OPEN_LOUD_A0_E03 (Autodesk Fusion 360 design; units mm, degrees)
part number: 2026-11-09-21-09-22-943
part number: 2026-11-09-21-09-23-218
part number: 2026-11-09-21-09-23-288
part number: 2026-11-09-21-09-23-386
part number: 2026-11-09-21-09-23-510
part number: 2026-11-09-21-09-23-669
part number: 2026-11-09-21-09-23-859
part number: 2026-11-09-21-09-24-690
part number: 2026-11-09-21-09-37-670
part number: 2026-11-09-21-09-45-890
part number: 2026-11-09-21-09-47-234
part number: 2026-11-09-21-09-48-583
part number: 2026-11-09-21-09-49-964
part number: 2026-11-09-21-09-52-239
part number: 2026-11-09-21-09-53-688
part number: 2026-11-09-21-09-55-178
part number: 2026-11-09-21-09-56-657
part number: 2026-11-09-21-09-58-092
part number: 2026-11-09-21-10-02-668
part number: 2026-11-09-21-10-08-469
part number: 2026-11-09-21-10-09-806
part number: 2026-11-09-21-14-51-726
part number: 2026-11-09-21-15-00-511
part number: 2026-11-09-21-15-10-046
part number: 2026-11-09-21-15-20-423
part number: 2026-11-09-21-15-31-572
part number: 2026-11-09-21-15-43-577
part number: 2026-11-09-21-15-56-782
part number: 2026-11-09-21-16-10-440
part number: 2026-11-09-21-16-24-862
part number: 2026-11-09-21-16-40-177
Autodesk Fusion 360 part; units mm, degrees
(part 1 of 3)
ref_plane "Arbeitsebene1" through (0, 0, 0) normal (0, 0, 1) x (1, 0, 0) in component "Side_left"
sketch "Skizze1" plane through (0, 0, 0) normal (0, 0, 1) x (1, 0, 0) in component "Side_left"
  line L0 (0, 0) -> (12, 0)
  line L1 (12, 0) -> (12, 560)
  line L2 (12, 560) -> (0, 560)
  line L3 (0, 560) -> (0, 0)
  dimension "d63" = 12
  dimension "d64" = 560
  constraint horizontal L0
  constraint horizontal L2
  constraint vertical L1
  constraint vertical L3
  constraint coincident L0.start L3.end
  measures "d63" horizontal distance of L0.start L0.end
  measures "d64" vertical distance of L0.end L1.end
extrude "Side_left" add sketch "Skizze1" along normal blind 300 makes body 1 in component "Side_left"
ref_plane "Arbeitsebene1" through (0, 0, 0) normal (0, 0, 1) x (1, 0, 0) in component "Side_right"
sketch "Skizze1 (2)" plane through (0, 0, 0) normal (0, 0, 1) x (1, 0, 0) in component "Side_right"
  line L0 (318, 0) -> (330, 0)
  line L1 (330, 0) -> (330, 560)
  line L2 (330, 560) -> (318, 560)
  line L3 (318, 560) -> (318, 0)
  dimension "d69" = 318
  dimension "d70" = 12
  dimension "d71" = 560
  constraint horizontal L0
  constraint horizontal L2
  constraint vertical L1
  constraint vertical L3
  constraint horizontal origin L0.start
  measures "d69" horizontal distance of origin L0.start
  measures "d70" horizontal distance of L0.start L0.end
  measures "d71" vertical distance of L0.end L1.end
extrude "Side_right" add sketch "Skizze1 (2)" along normal blind 300 separate body makes body 2 in component "Side_right"
ref_plane "Arbeitsebene1" through (0, 0, 0) normal (0, 0, 1) x (1, 0, 0) in component "Bottom"
sketch "Skizze1 (3)" plane through (0, 0, 0) normal (0, 0, 1) x (1, 0, 0) in component "Bottom"
  line L0 (12, 0) -> (318, 0)
  line L1 (318, 0) -> (318, 12)
  line L2 (318, 12) -> (12, 12)
  line L3 (12, 12) -> (12, 0)
  dimension "d76" = 12
  dimension "d77" = 306
  dimension "d78" = 12
  constraint horizontal L0
  constraint horizontal L2
  constraint vertical L1
  constraint vertical L3
  constraint horizontal origin L0.start
  measures "d76" horizontal distance of origin L0.start
  measures "d77" horizontal distance of L0.start L0.end
  measures "d78" vertical distance of L0.end L1.end
extrude "Bottom" add sketch "Skizze1 (3)" along normal blind 300 separate body makes body 3 in component "Bottom"
ref_plane "Arbeitsebene1" through (0, 0, 0) normal (0, 0, 1) x (1, 0, 0) in component "Top"
sketch "Skizze1 (4)" plane through (0, 0, 0) normal (0, 0, 1) x (1, 0, 0) in component "Top"
  line L0 (12, 548) -> (318, 548)
  line L1 (318, 548) -> (318, 560)
  line L2 (318, 560) -> (12, 560)
  line L3 (12, 560) -> (12, 548)
  dimension "d83" = 12
  dimension "d84" = 548
  dimension "d85" = 306
  dimension "d86" = 12
  constraint horizontal L0
  constraint horizontal L2
  constraint vertical L1
  constraint vertical L3
  measures "d83" horizontal distance of origin L0.start
  measures "d84" vertical distance of origin L0.start
  measures "d85" horizontal distance of L0.start L0.end
  measures "d86" vertical distance of L0.end L1.end
extrude "Top" add sketch "Skizze1 (4)" along normal blind 300 separate body makes body 4 in component "Top"
ref_plane "Arbeitsebene1" through (0, 0, 0) normal (0, 0, 1) x (1, 0, 0) in component "Baffle"
sketch "Skizze1 (5)" plane through (0, 0, 0) normal (0, 0, 1) x (1, 0, 0) in component "Baffle"
  line L0 (12, 12) -> (318, 12)
  line L1 (318, 12) -> (318, 548)
  line L2 (318, 548) -> (12, 548)
  line L3 (12, 548) -> (12, 12)
  dimension "d91" = 12
  dimension "d92" = 12
  dimension "d93" = 306
  dimension "d94" = 536
  constraint horizontal L0
  constraint horizontal L2
  constraint vertical L1
  constraint vertical L3
  measures "d91" horizontal distance of origin L0.start
  measures "d92" vertical distance of origin L0.start
  measures "d93" horizontal distance of L0.start L0.end
  measures "d94" vertical distance of L0.end L1.end
extrude "Baffle" add sketch "Skizze1 (5)" along normal blind 12 separate body makes body 5 in component "Baffle"
ref_plane "Arbeitsebene1" through (0, 0, 288) normal (0, 0, 1) x (1, 0, 0) in component "Rear_removable"
sketch "Skizze1 (6)" plane through (0, 0, 288) normal (0, 0, 1) x (1, 0, 0) in component "Rear_removable"
  line L0 (12, 12) -> (318, 12)
  line L1 (318, 12) -> (318, 548)
  line L2 (318, 548) -> (12, 548)
  line L3 (12, 548) -> (12, 12)
  dimension "d99" = 12
  dimension "d100" = 12
  dimension "d101" = 306
  dimension "d102" = 536
  constraint horizontal L0
  constraint horizontal L2
  constraint vertical L1
  constraint vertical L3
  measures "d99" horizontal distance of origin L0.start
  measures "d100" vertical distance of origin L0.start
  measures "d101" horizontal distance of L0.start L0.end
  measures "d102" vertical distance of L0.end L1.end
extrude "Rear_removable" add sketch "Skizze1 (6)" along normal blind 12 separate body makes body 6 in component "Rear_removable"
ref_plane "Arbeitsebene2" through (0, 0, 0) normal (0, 0, 1) x (1, 0, 0) in component "Baffle"
sketch "Skizze2" plane through (0, 0, 0) normal (0, 0, 1) x (1, 0, 0) in component "Baffle"
  circle A0 centre (165, 260) radius 117.15
  dimension "d107" = 165
  dimension "d108" = 260
  dimension "d109" = 234.3
  measures "d107" horizontal distance of origin A0.centre
  measures "d108" vertical distance of origin A0.centre
  measures "d109" diameter of A0
extrude "LF_cut" cut sketch "Skizze2" along normal blind 12 bodies 5 in component "Baffle"
ref_plane "Arbeitsebene3" through (0, 0, 0) normal (0, 0, 1) x (1, 0, 0) in component "Baffle"
sketch "Skizze3" plane through (0, 0, 0) normal (0, 0, 1) x (1, 0, 0) in component "Baffle"
  circle A0 centre (165, 70) radius 48.9864
  dimension "d114" = 165
  dimension "d115" = 70
  dimension "d116" = 97.9728
  measures "d114" horizontal distance of origin A0.centre
  measures "d115" vertical distance of origin A0.centre
  measures "d116" diameter of A0
extrude "Port_cut" cut sketch "Skizze3" along normal blind 12 bodies 5 in component "Baffle"
ref_plane "Arbeitsebene4" through (0, 0, 0) normal (0, 0, 1) x (1, 0, 0) in component "Baffle"
sketch "Skizze4" plane through (0, 0, 0) normal (0, 0, 1) x (1, 0, 0) in component "Baffle"
  line L0 (113, 418) -> (217, 418)
  line L1 (217, 418) -> (217, 522)
  line L2 (217, 522) -> (113, 522)
  line L3 (113, 522) -> (113, 418)
  dimension "d121" = 113
  dimension "d122" = 418
  dimension "d123" = 104
  dimension "d124" = 104
  constraint horizontal L0
  constraint horizontal L2
  constraint vertical L1
  constraint vertical L3
  measures "d121" horizontal distance of origin L0.start
  measures "d122" vertical distance of origin L0.start
  measures "d123" horizontal distance of L0.start L0.end
  measures "d124" vertical distance of L0.end L1.end
extrude "Horn_cut" cut sketch "Skizze4" along normal blind 12 bodies 5 in component "Baffle"
ref_plane "Arbeitsebene1" through (0, 0, 12) normal (0, 0, 1) x (1, 0, 0) in component "Baffle_inner_lamination"
sketch "Skizze1 (7)" plane through (0, 0, 12) normal (0, 0, 1) x (1, 0, 0) in component "Baffle_inner_lamination"
  line L0 (12, 12) -> (318, 12)
  line L1 (318, 12) -> (318, 548)
  line L2 (318, 548) -> (12, 548)
  line L3 (12, 548) -> (12, 12)
  dimension "d129" = 12
  dimension "d130" = 12
  dimension "d131" = 306
  dimension "d132" = 536
  constraint horizontal L0
  constraint horizontal L2
  constraint vertical L1
  constraint vertical L3
  measures "d129" horizontal distance of origin L0.start
  measures "d130" vertical distance of origin L0.start
  measures "d131" horizontal distance of L0.start L0.end
  measures "d132" vertical distance of L0.end L1.end
extrude "Baffle_inner_lamination" add sketch "Skizze1 (7)" along normal blind 12 separate body makes body 7 in component "Baffle_inner_lamination"
ref_plane "Arbeitsebene2" through (0, 0, 12) normal (0, 0, 1) x (1, 0, 0) in component "Baffle_inner_lamination"
sketch "Skizze2 (2)" plane through (0, 0, 12) normal (0, 0, 1) x (1, 0, 0) in component "Baffle_inner_lamination"
  circle A0 centre (165, 260) radius 117.15
  dimension "d137" = 165
  dimension "d138" = 260
  dimension "d139" = 234.3
  measures "d137" horizontal distance of origin A0.centre
  measures "d138" vertical distance of origin A0.centre
  measures "d139" diameter of A0
extrude "LF_reinforcement_cut" cut sketch "Skizze2 (2)" along normal blind 12 bodies 7 in component "Baffle_inner_lamination"
ref_plane "Arbeitsebene3" through (0, 0, 12) normal (0, 0, 1) x (1, 0, 0) in component "Baffle_inner_lamination"
sketch "Skizze3 (2)" plane through (0, 0, 12) normal (0, 0, 1) x (1, 0, 0) in component "Baffle_inner_lamination"
  circle A0 centre (165, 70) radius 48.9864
  dimension "d144" = 165
  dimension "d145" = 70
  dimension "d146" = 97.9728
  measures "d144" horizontal distance of origin A0.centre
  measures "d145" vertical distance of origin A0.centre
  measures "d146" diameter of A0
extrude "Port_reinforcement_cut" cut sketch "Skizze3 (2)" along normal blind 12 bodies 7 in component "Baffle_inner_lamination"
ref_plane "Arbeitsebene4" through (0, 0, 12) normal (0, 0, 1) x (1, 0, 0) in component "Baffle_inner_lamination"
sketch "Skizze4 (2)" plane through (0, 0, 12) normal (0, 0, 1) x (1, 0, 0) in component "Baffle_inner_lamination"
  line L0 (113, 418) -> (217, 418)
  line L1 (217, 418) -> (217, 522)
  line L2 (217, 522) -> (113, 522)
  line L3 (113, 522) -> (113, 418)
  dimension "d151" = 113
  dimension "d152" = 418
  dimension "d153" = 104
  dimension "d154" = 104
  constraint horizontal L0
  constraint horizontal L2
  constraint vertical L1
  constraint vertical L3
  measures "d151" horizontal distance of origin L0.start
  measures "d152" vertical distance of origin L0.start
  measures "d153" horizontal distance of L0.start L0.end
  measures "d154" vertical distance of L0.end L1.end
extrude "Horn_reinforcement_cut" cut sketch "Skizze4 (2)" along normal blind 12 bodies 7 in component "Baffle_inner_lamination"
ref_plane "Arbeitsebene5" through (0, 0, 0) normal (0, 0, 1) x (1, 0, 0) in component "Baffle"
sketch "Skizze5" plane through (0, 0, 0) normal (0, 0, 1) x (1, 0, 0) in component "Baffle"
  circle A0 centre (286.9, 260) radius 2.75
  dimension "d159" = 286.9
  dimension "d160" = 260
  dimension "d161" = 5.5
  measures "d159" horizontal distance of origin A0.centre
  measures "d160" vertical distance of origin A0.centre
  measures "d161" diameter of A0
extrude "LF_M5_bore_0" cut sketch "Skizze5" along normal blind 12 bodies 5 in component "Baffle"
ref_plane "Arbeitsebene6" through (0, 0, 0) normal (0, 0, 1) x (1, 0, 0) in component "Baffle"
sketch "Skizze6" plane through (0, 0, 0) normal (0, 0, 1) x (1, 0, 0) in component "Baffle"
  circle A0 centre (251.1963, 346.1963) radius 2.75
  dimension "d166" = 251.1963
  dimension "d167" = 346.1963
  dimension "d168" = 5.5
  measures "d166" horizontal distance of origin A0.centre
  measures "d167" vertical distance of origin A0.centre
  measures "d168" diameter of A0
extrude "LF_M5_bore_1" cut sketch "Skizze6" along normal blind 12 bodies 5 in component "Baffle"
ref_plane "Arbeitsebene7" through (0, 0, 0) normal (0, 0, 1) x (1, 0, 0) in component "Baffle"
sketch "Skizze7" plane through (0, 0, 0) normal (0, 0, 1) x (1, 0, 0) in component "Baffle"
  circle A0 centre (165, 381.9) radius 2.75
  dimension "d173" = 165
  dimension "d174" = 381.9
  dimension "d175" = 5.5
  measures "d173" horizontal distance of origin A0.centre
  measures "d174" vertical distance of origin A0.centre
  measures "d175" diameter of A0
extrude "LF_M5_bore_2" cut sketch "Skizze7" along normal blind 12 bodies 5 in component "Baffle"
ref_plane "Arbeitsebene8" through (0, 0, 0) normal (0, 0, 1) x (1, 0, 0) in component "Baffle"
sketch "Skizze8" plane through (0, 0, 0) normal (0, 0, 1) x (1, 0, 0) in component "Baffle"
  circle A0 centre (78.8037, 346.1963) radius 2.75
  dimension "d180" = 78.8037
  dimension "d181" = 346.1963
  dimension "d182" = 5.5
  measures "d180" horizontal distance of origin A0.centre
  measures "d181" vertical distance of origin A0.centre
  measures "d182" diameter of A0
extrude "LF_M5_bore_3" cut sketch "Skizze8" along normal blind 12 bodies 5 in component "Baffle"
ref_plane "Arbeitsebene9" through (0, 0, 0) normal (0, 0, 1) x (1, 0, 0) in component "Baffle"
sketch "Skizze9" plane through (0, 0, 0) normal (0, 0, 1) x (1, 0, 0) in component "Baffle"
  circle A0 centre (43.1, 260) radius 2.75
  dimension "d187" = 43.1
  dimension "d188" = 260
  dimension "d189" = 5.5
  measures "d187" horizontal distance of origin A0.centre
  measures "d188" vertical distance of origin A0.centre
  measures "d189" diameter of A0
extrude "LF_M5_bore_4" cut sketch "Skizze9" along normal blind 12 bodies 5 in component "Baffle"
ref_plane "Arbeitsebene10" through (0, 0, 0) normal (0, 0, 1) x (1, 0, 0) in component "Baffle"
sketch "Skizze10" plane through (0, 0, 0) normal (0, 0, 1) x (1, 0, 0) in component "Baffle"
  circle A0 centre (78.8037, 173.8037) radius 2.75
  dimension "d194" = 78.8037
  dimension "d195" = 173.8037
  dimension "d196" = 5.5
  measures "d194" horizontal distance of origin A0.centre
  measures "d195" vertical distance of origin A0.centre
  measures "d196" diameter of A0
extrude "LF_M5_bore_5" cut sketch "Skizze10" along normal blind 12 bodies 5 in component "Baffle"
ref_plane "Arbeitsebene11" through (0, 0, 0) normal (0, 0, 1) x (1, 0, 0) in component "Baffle"
sketch "Skizze11" plane through (0, 0, 0) normal (0, 0, 1) x (1, 0, 0) in component "Baffle"
  circle A0 centre (165, 138.1) radius 2.75
  dimension "d201" = 165
  dimension "d202" = 138.1
  dimension "d203" = 5.5
  measures "d201" horizontal distance of origin A0.centre
  measures "d202" vertical distance of origin A0.centre
  measures "d203" diameter of A0
extrude "LF_M5_bore_6" cut sketch "Skizze11" along normal blind 12 bodies 5 in component "Baffle"
ref_plane "Arbeitsebene12" through (0, 0, 0) normal (0, 0, 1) x (1, 0, 0) in component "Baffle"
sketch "Skizze12" plane through (0, 0, 0) normal (0, 0, 1) x (1, 0, 0) in component "Baffle"
  circle A0 centre (251.1963, 173.8037) radius 2.75
  dimension "d208" = 251.1963
  dimension "d209" = 173.8037
  dimension "d210" = 5.5
  measures "d208" horizontal distance of origin A0.centre
  measures "d209" vertical distance of origin A0.centre
  measures "d210" diameter of A0
extrude "LF_M5_bore_7" cut sketch "Skizze12" along normal blind 12 bodies 5 in component "Baffle"
ref_plane "Arbeitsebene13" through (0, 0, 0) normal (0, 0, 1) x (1, 0, 0) in component "Baffle"
sketch "Skizze13" plane through (0, 0, 0) normal (0, 0, 1) x (1, 0, 0) in component "Baffle"
  circle A0 centre (108, 413) radius 2.25
  dimension "d215" = 108
  dimension "d216" = 413
  dimension "d217" = 4.5
  measures "d215" horizontal distance of origin A0.centre
  measures "d216" vertical distance of origin A0.centre
  measures "d217" diameter of A0
extrude "Horn_M4_bore" cut sketch "Skizze13" along normal blind 12 bodies 5 in component "Baffle"
ref_plane "Arbeitsebene14" through (0, 0, 0) normal (0, 0, 1) x (1, 0, 0) in component "Baffle"
sketch "Skizze14" plane through (0, 0, 0) normal (0, 0, 1) x (1, 0, 0) in component "Baffle"
  circle A0 centre (108, 527) radius 2.25
  dimension "d222" = 108
  dimension "d223" = 527
  dimension "d224" = 4.5
  measures "d222" horizontal distance of origin A0.centre
  measures "d223" vertical distance of origin A0.centre
  measures "d224" diameter of A0
extrude "Horn_M4_bore (1)" cut sketch "Skizze14" along normal blind 12 bodies 5 in component "Baffle"
ref_plane "Arbeitsebene15" through (0, 0, 0) normal (0, 0, 1) x (1, 0, 0) in component "Baffle"
sketch "Skizze15" plane through (0, 0, 0) normal (0, 0, 1) x (1, 0, 0) in component "Baffle"
  circle A0 centre (222, 413) radius 2.25
  dimension "d229" = 222
  dimension "d230" = 413
  dimension "d231" = 4.5
  measures "d229" horizontal distance of origin A0.centre
  measures "d230" vertical distance of origin A0.centre
  measures "d231" diameter of A0
extrude "Horn_M4_bore (2)" cut sketch "Skizze15" along normal blind 12 bodies 5 in component "Baffle"
ref_plane "Arbeitsebene16" through (0, 0, 0) normal (0, 0, 1) x (1, 0, 0) in component "Baffle"
sketch "Skizze16" plane through (0, 0, 0) normal (0, 0, 1) x (1, 0, 0) in component "Baffle"
  circle A0 centre (222, 527) radius 2.25
  dimension "d236" = 222
  dimension "d237" = 527
  dimension "d238" = 4.5
  measures "d236" horizontal distance of origin A0.centre
  measures "d237" vertical distance of origin A0.centre
  measures "d238" diameter of A0
extrude "Horn_M4_bore (3)" cut sketch "Skizze16" along normal blind 12 bodies 5 in component "Baffle"
ref_plane "Arbeitsebene5" through (0, 0, 12) normal (0, 0, 1) x (1, 0, 0) in component "Baffle_inner_lamination"
sketch "Skizze5 (2)" plane through (0, 0, 12) normal (0, 0, 1) x (1, 0, 0) in component "Baffle_inner_lamination"
  circle A0 centre (286.9, 260) radius 2.75
  dimension "d243" = 286.9
  dimension "d244" = 260
  dimension "d245" = 5.5
  measures "d243" horizontal distance of origin A0.centre
  measures "d244" vertical distance of origin A0.centre
  measures "d245" diameter of A0
extrude "LF_M5_bore_0'" cut sketch "Skizze5 (2)" along normal blind 12 bodies 7 in component "Baffle_inner_lamination"
ref_plane "Arbeitsebene6" through (0, 0, 12) normal (0, 0, 1) x (1, 0, 0) in component "Baffle_inner_lamination"
sketch "Skizze6 (2)" plane through (0, 0, 12) normal (0, 0, 1) x (1, 0, 0) in component "Baffle_inner_lamination"
  circle A0 centre (251.1963, 346.1963) radius 2.75
  dimension "d250" = 251.1963
  dimension "d251" = 346.1963
  dimension "d252" = 5.5
  measures "d250" horizontal distance of origin A0.centre
  measures "d251" vertical distance of origin A0.centre
  measures "d252" diameter of A0
extrude "LF_M5_bore_1'" cut sketch "Skizze6 (2)" along normal blind 12 bodies 7 in component "Baffle_inner_lamination"
ref_plane "Arbeitsebene7" through (0, 0, 12) normal (0, 0, 1) x (1, 0, 0) in component "Baffle_inner_lamination"
sketch "Skizze7 (2)" plane through (0, 0, 12) normal (0, 0, 1) x (1, 0, 0) in component "Baffle_inner_lamination"
  circle A0 centre (165, 381.9) radius 2.75
  dimension "d257" = 165
  dimension "d258" = 381.9
  dimension "d259" = 5.5
  measures "d257" horizontal distance of origin A0.centre
  measures "d258" vertical distance of origin A0.centre
  measures "d259" diameter of A0
extrude "LF_M5_bore_2'" cut sketch "Skizze7 (2)" along normal blind 12 bodies 7 in component "Baffle_inner_lamination"
ref_plane "Arbeitsebene8" through (0, 0, 12) normal (0, 0, 1) x (1, 0, 0) in component "Baffle_inner_lamination"
sketch "Skizze8 (2)" plane through (0, 0, 12) normal (0, 0, 1) x (1, 0, 0) in component "Baffle_inner_lamination"
  circle A0 centre (78.8037, 346.1963) radius 2.75
  dimension "d264" = 78.8037
  dimension "d265" = 346.1963
  dimension "d266" = 5.5
  measures "d264" horizontal distance of origin A0.centre
  measures "d265" vertical distance of origin A0.centre
  measures "d266" diameter of A0
extrude "LF_M5_bore_3'" cut sketch "Skizze8 (2)" along normal blind 12 bodies 7 in component "Baffle_inner_lamination"
ref_plane "Arbeitsebene9" through (0, 0, 12) normal (0, 0, 1) x (1, 0, 0) in component "Baffle_inner_lamination"
sketch "Skizze9 (2)" plane through (0, 0, 12) normal (0, 0, 1) x (1, 0, 0) in component "Baffle_inner_lamination"
  circle A0 centre (43.1, 260) radius 2.75
  dimension "d271" = 43.1
  dimension "d272" = 260
  dimension "d273" = 5.5
  measures "d271" horizontal distance of origin A0.centre
  measures "d272" vertical distance of origin A0.centre
  measures "d273" diameter of A0
extrude "LF_M5_bore_4'" cut sketch "Skizze9 (2)" along normal blind 12 bodies 7 in component "Baffle_inner_lamination"
ref_plane "Arbeitsebene10" through (0, 0, 12) normal (0, 0, 1) x (1, 0, 0) in component "Baffle_inner_lamination"
sketch "Skizze10 (2)" plane through (0, 0, 12) normal (0, 0, 1) x (1, 0, 0) in component "Baffle_inner_lamination"
  circle A0 centre (78.8037, 173.8037) radius 2.75
  dimension "d278" = 78.8037
  dimension "d279" = 173.8037
  dimension "d280" = 5.5
  measures "d278" horizontal distance of origin A0.centre
  measures "d279" vertical distance of origin A0.centre
  measures "d280" diameter of A0
extrude "LF_M5_bore_5'" cut sketch "Skizze10 (2)" along normal blind 12 bodies 7 in component "Baffle_inner_lamination"
ref_plane "Arbeitsebene11" through (0, 0, 12) normal (0, 0, 1) x (1, 0, 0) in component "Baffle_inner_lamination"
sketch "Skizze11 (2)" plane through (0, 0, 12) normal (0, 0, 1) x (1, 0, 0) in component "Baffle_inner_lamination"
  circle A0 centre (165, 138.1) radius 2.75
  dimension "d285" = 165
  dimension "d286" = 138.1
  dimension "d287" = 5.5
  measures "d285" horizontal distance of origin A0.centre
  measures "d286" vertical distance of origin A0.centre
  measures "d287" diameter of A0
extrude "LF_M5_bore_6'" cut sketch "Skizze11 (2)" along normal blind 12 bodies 7 in component "Baffle_inner_lamination"
ref_plane "Arbeitsebene12" through (0, 0, 12) normal (0, 0, 1) x (1, 0, 0) in component "Baffle_inner_lamination"
sketch "Skizze12 (2)" plane through (0, 0, 12) normal (0, 0, 1) x (1, 0, 0) in component "Baffle_inner_lamination"
  circle A0 centre (251.1963, 173.8037) radius 2.75
  dimension "d292" = 251.1963
  dimension "d293" = 173.8037
  dimension "d294" = 5.5
  measures "d292" horizontal distance of origin A0.centre
  measures "d293" vertical distance of origin A0.centre
  measures "d294" diameter of A0
extrude "LF_M5_bore_7'" cut sketch "Skizze12 (2)" along normal blind 12 bodies 7 in component "Baffle_inner_lamination"
ref_plane "Arbeitsebene13" through (0, 0, 12) normal (0, 0, 1) x (1, 0, 0) in component "Baffle_inner_lamination"
sketch "Skizze13 (2)" plane through (0, 0, 12) normal (0, 0, 1) x (1, 0, 0) in component "Baffle_inner_lamination"
  circle A0 centre (108, 413) radius 2.25
  dimension "d299" = 108
  dimension "d300" = 413
  dimension "d301" = 4.5
  measures "d299" horizontal distance of origin A0.centre
  measures "d300" vertical distance of origin A0.centre
  measures "d301" diameter of A0
extrude "Horn_M4_bore'" cut sketch "Skizze13 (2)" along normal blind 12 bodies 7 in component "Baffle_inner_lamination"
ref_plane "Arbeitsebene14" through (0, 0, 12) normal (0, 0, 1) x (1, 0, 0) in component "Baffle_inner_lamination"
sketch "Skizze14 (2)" plane through (0, 0, 12) normal (0, 0, 1) x (1, 0, 0) in component "Baffle_inner_lamination"
  circle A0 centre (108, 527) radius 2.25
  dimension "d306" = 108
  dimension "d307" = 527
  dimension "d308" = 4.5
  measures "d306" horizontal distance of origin A0.centre
  measures "d307" vertical distance of origin A0.centre
  measures "d308" diameter of A0
extrude "Horn_M4_bore (1)'" cut sketch "Skizze14 (2)" along normal blind 12 bodies 7 in component "Baffle_inner_lamination"
ref_plane "Arbeitsebene15" through (0, 0, 12) normal (0, 0, 1) x (1, 0, 0) in component "Baffle_inner_lamination"
sketch "Skizze15 (2)" plane through (0, 0, 12) normal (0, 0, 1) x (1, 0, 0) in component "Baffle_inner_lamination"
  circle A0 centre (222, 413) radius 2.25
  dimension "d313" = 222
  dimension "d314" = 413
  dimension "d315" = 4.5
  measures "d313" horizontal distance of origin A0.centre
  measures "d314" vertical distance of origin A0.centre
  measures "d315" diameter of A0
extrude "Horn_M4_bore (2)'" cut sketch "Skizze15 (2)" along normal blind 12 bodies 7 in component "Baffle_inner_lamination"
ref_plane "Arbeitsebene16" through (0, 0, 12) normal (0, 0, 1) x (1, 0, 0) in component "Baffle_inner_lamination"
sketch "Skizze16 (2)" plane through (0, 0, 12) normal (0, 0, 1) x (1, 0, 0) in component "Baffle_inner_lamination"
  circle A0 centre (222, 527) radius 2.25
  dimension "d320" = 222
  dimension "d321" = 527
  dimension "d322" = 4.5
  measures "d320" horizontal distance of origin A0.centre
  measures "d321" vertical distance of origin A0.centre
  measures "d322" diameter of A0
extrude "Horn_M4_bore (3)'" cut sketch "Skizze16 (2)" along normal blind 12 bodies 7 in component "Baffle_inner_lamination"
ref_plane "Arbeitsebene1" through (0, 0, 24) normal (0, 0, 1) x (1, 0, 0) in component "LF_steel_backing_ring_candidate"
sketch "Skizze1 (8)" plane through (0, 0, 24) normal (0, 0, 1) x (1, 0, 0) in component "LF_steel_backing_ring_candidate"
  circle A0 centre (165, 260) radius 140
  circle A1 centre (165, 260) radius 110
  dimension "d327" = 165
  dimension "d328" = 260
  dimension "d329" = 280
  dimension "d330" = 220
  constraint concentric A0 A1
  measures "d327" horizontal distance of origin A0.centre
  measures "d328" vertical distance of origin A0.centre
  measures "d329" diameter of A0
  measures "d330" diameter of A1
extrude "Steel_backing_ring" add sketch "Skizze1 (8)" along normal blind 3 separate body makes body 8 in component "LF_steel_backing_ring_candidate"
ref_plane "Arbeitsebene2" through (0, 0, 24) normal (0, 0, 1) x (1, 0, 0) in component "LF_steel_backing_ring_candidate"
sketch "Skizze2 (3)" plane through (0, 0, 24) normal (0, 0, 1) x (1, 0, 0) in component "LF_steel_backing_ring_candidate"
  circle A0 centre (165, 70) radius 49.4864
  dimension "d335" = 165
  dimension "d336" = 70
  dimension "d337" = 98.9728
  measures "d335" horizontal distance of origin A0.centre
  measures "d336" vertical distance of origin A0.centre
  measures "d337" diameter of A0
ref_plane "Arbeitsebene3" through (0, 0, 24) normal (0, 0, 1) x (1, 0, 0) in component "LF_steel_backing_ring_candidate"
sketch "Skizze3 (3)" plane through (0, 0, 24) normal (0, 0, 1) x (1, 0, 0) in component "LF_steel_backing_ring_candidate"
  circle A0 centre (286.9, 260) radius 2.75
  dimension "d342" = 286.9
  dimension "d343" = 260
  dimension "d344" = 5.5
  measures "d342" horizontal distance of origin A0.centre
  measures "d343" vertical distance of origin A0.centre
  measures "d344" diameter of A0
extrude "Steel_M5_bore_0" cut sketch "Skizze3 (3)" along normal blind 3 bodies 8 in component "LF_steel_backing_ring_candidate"
ref_plane "Arbeitsebene4" through (0, 0, 24) normal (0, 0, 1) x (1, 0, 0) in component "LF_steel_backing_ring_candidate"
sketch "Skizze4 (3)" plane through (0, 0, 24) normal (0, 0, 1) x (1, 0, 0) in component "LF_steel_backing_ring_candidate"
  circle A0 centre (251.1963, 346.1963) radius 2.75
  dimension "d349" = 251.1963
  dimension "d350" = 346.1963
  dimension "d351" = 5.5
  measures "d349" horizontal distance of origin A0.centre
  measures "d350" vertical distance of origin A0.centre
  measures "d351" diameter of A0
extrude "Steel_M5_bore_1" cut sketch "Skizze4 (3)" along normal blind 3 bodies 8 in component "LF_steel_backing_ring_candidate"
ref_plane "Arbeitsebene5" through (0, 0, 24) normal (0, 0, 1) x (1, 0, 0) in component "LF_steel_backing_ring_candidate"
sketch "Skizze5 (3)" plane through (0, 0, 24) normal (0, 0, 1) x (1, 0, 0) in component "LF_steel_backing_ring_candidate"
  circle A0 centre (165, 381.9) radius 2.75
  dimension "d356" = 165
  dimension "d357" = 381.9
  dimension "d358" = 5.5
  measures "d356" horizontal distance of origin A0.centre
  measures "d357" vertical distance of origin A0.centre
  measures "d358" diameter of A0
extrude "Steel_M5_bore_2" cut sketch "Skizze5 (3)" along normal blind 3 bodies 8 in component "LF_steel_backing_ring_candidate"
ref_plane "Arbeitsebene6" through (0, 0, 24) normal (0, 0, 1) x (1, 0, 0) in component "LF_steel_backing_ring_candidate"
sketch "Skizze6 (3)" plane through (0, 0, 24) normal (0, 0, 1) x (1, 0, 0) in component "LF_steel_backing_ring_candidate"
  circle A0 centre (78.8037, 346.1963) radius 2.75
  dimension "d363" = 78.8037
  dimension "d364" = 346.1963
  dimension "d365" = 5.5
  measures "d363" horizontal distance of origin A0.centre
  measures "d364" vertical distance of origin A0.centre
  measures "d365" diameter of A0
extrude "Steel_M5_bore_3" cut sketch "Skizze6 (3)" along normal blind 3 bodies 8 in component "LF_steel_backing_ring_candidate"
ref_plane "Arbeitsebene7" through (0, 0, 24) normal (0, 0, 1) x (1, 0, 0) in component "LF_steel_backing_ring_candidate"
sketch "Skizze7 (3)" plane through (0, 0, 24) normal (0, 0, 1) x (1, 0, 0) in component "LF_steel_backing_ring_candidate"
  circle A0 centre (43.1, 260) radius 2.75
  dimension "d370" = 43.1
  dimension "d371" = 260
  dimension "d372" = 5.5
  measures "d370" horizontal distance of origin A0.centre
  measures "d371" vertical distance of origin A0.centre
  measures "d372" diameter of A0
extrude "Steel_M5_bore_4" cut sketch "Skizze7 (3)" along normal blind 3 bodies 8 in component "LF_steel_backing_ring_candidate"
ref_plane "Arbeitsebene8" through (0, 0, 24) normal (0, 0, 1) x (1, 0, 0) in component "LF_steel_backing_ring_candidate"
sketch "Skizze8 (3)" plane through (0, 0, 24) normal (0, 0, 1) x (1, 0, 0) in component "LF_steel_backing_ring_candidate"
  circle A0 centre (78.8037, 173.8037) radius 2.75
  dimension "d377" = 78.8037
  dimension "d378" = 173.8037
  dimension "d379" = 5.5
  measures "d377" horizontal distance of origin A0.centre
  measures "d378" vertical distance of origin A0.centre
  measures "d379" diameter of A0
extrude "Steel_M5_bore_5" cut sketch "Skizze8 (3)" along normal blind 3 bodies 8 in component "LF_steel_backing_ring_candidate"
ref_plane "Arbeitsebene9" through (0, 0, 24) normal (0, 0, 1) x (1, 0, 0) in component "LF_steel_backing_ring_candidate"
sketch "Skizze9 (3)" plane through (0, 0, 24) normal (0, 0, 1) x (1, 0, 0) in component "LF_steel_backing_ring_candidate"
  circle A0 centre (165, 138.1) radius 2.75
  dimension "d384" = 165
  dimension "d385" = 138.1
  dimension "d386" = 5.5
  measures "d384" horizontal distance of origin A0.centre
  measures "d385" vertical distance of origin A0.centre
  measures "d386" diameter of A0
extrude "Steel_M5_bore_6" cut sketch "Skizze9 (3)" along normal blind 3 bodies 8 in component "LF_steel_backing_ring_candidate"
ref_plane "Arbeitsebene10" through (0, 0, 24) normal (0, 0, 1) x (1, 0, 0) in component "LF_steel_backing_ring_candidate"
sketch "Skizze10 (3)" plane through (0, 0, 24) normal (0, 0, 1) x (1, 0, 0) in component "LF_steel_backing_ring_candidate"
  circle A0 centre (251.1963, 173.8037) radius 2.75
  dimension "d391" = 251.1963
  dimension "d392" = 173.8037
  dimension "d393" = 5.5
  measures "d391" horizontal distance of origin A0.centre
  measures "d392" vertical distance of origin A0.centre
  measures "d393" diameter of A0
extrude "Steel_M5_bore_7" cut sketch "Skizze10 (3)" along normal blind 3 bodies 8 in component "LF_steel_backing_ring_candidate"
ref_plane "Arbeitsebene1" through (0, 0, 268) normal (0, 0, 1) x (1, 0, 0) in component "Rear_cleat_left"
sketch "Skizze1 (9)" plane through (0, 0, 268) normal (0, 0, 1) x (1, 0, 0) in component "Rear_cleat_left"
  line L0 (12, 12) -> (32, 12)
  line L1 (32, 12) -> (32, 548)
  line L2 (32, 548) -> (12, 548)
  line L3 (12, 548) -> (12, 12)
  dimension "d398" = 12
  dimension "d399" = 12
  dimension "d400" = 20
  dimension "d401" = 536
  constraint horizontal L0
  constraint horizontal L2
  constraint vertical L1
  constraint vertical L3
  measures "d398" horizontal distance of origin L0.start
  measures "d399" vertical distance of origin L0.start
  measures "d400" horizontal distance of L0.start L0.end
  measures "d401" vertical distance of L0.end L1.end
extrude "Rear_cleat_left" add sketch "Skizze1 (9)" along normal blind 20 separate body makes body 9 in component "Rear_cleat_left"
ref_plane "Arbeitsebene1" through (0, 0, 268) normal (0, 0, 1) x (1, 0, 0) in component "Rear_cleat_right"
sketch "Skizze1 (10)" plane through (0, 0, 268) normal (0, 0, 1) x (1, 0, 0) in component "Rear_cleat_right"
  line L0 (298, 12) -> (318, 12)
  line L1 (318, 12) -> (318, 548)
  line L2 (318, 548) -> (298, 548)
  line L3 (298, 548) -> (298, 12)
  dimension "d406" = 298
  dimension "d407" = 12
  dimension "d408" = 20
  dimension "d409" = 536
  constraint horizontal L0
  constraint horizontal L2
  constraint vertical L1
  constraint vertical L3
  measures "d406" horizontal distance of origin L0.start
  measures "d407" vertical distance of origin L0.start
  measures "d408" horizontal distance of L0.start L0.end
  measures "d409" vertical distance of L0.end L1.end
extrude "Rear_cleat_right" add sketch "Skizze1 (10)" along normal blind 20 separate body makes body 10 in component "Rear_cleat_right"
ref_plane "Arbeitsebene1" through (0, 0, 268) normal (0, 0, 1) x (1, 0, 0) in component "Rear_cleat_bottom"
sketch "Skizze1 (11)" plane through (0, 0, 268) normal (0, 0, 1) x (1, 0, 0) in component "Rear_cleat_bottom"
  line L0 (32, 12) -> (298, 12)
  line L1 (298, 12) -> (298, 32)
  line L2 (298, 32) -> (32, 32)
  line L3 (32, 32) -> (32, 12)
  dimension "d414" = 32
  dimension "d415" = 12
  dimension "d416" = 266
  dimension "d417" = 20
  constraint horizontal L0
  constraint horizontal L2
  constraint vertical L1
  constraint vertical L3
  measures "d414" horizontal distance of origin L0.start
  measures "d415" vertical distance of origin L0.start
  measures "d416" horizontal distance of L0.start L0.end
  measures "d417" vertical distance of L0.end L1.end
extrude "Rear_cleat_bottom" add sketch "Skizze1 (11)" along normal blind 20 separate body makes body 11 in component "Rear_cleat_bottom"
ref_plane "Arbeitsebene1" through (0, 0, 268) normal (0, 0, 1) x (1, 0, 0) in component "Rear_cleat_top"
sketch "Skizze1 (12)" plane through (0, 0, 268) normal (0, 0, 1) x (1, 0, 0) in component "Rear_cleat_top"
  line L0 (32, 528) -> (298, 528)
  line L1 (298, 528) -> (298, 548)
  line L2 (298, 548) -> (32, 548)
  line L3 (32, 548) -> (32, 528)
  dimension "d422" = 32
  dimension "d423" = 528
  dimension "d424" = 266
  dimension "d425" = 20
  constraint horizontal L0
  constraint horizontal L2
  constraint vertical L1
  constraint vertical L3
  measures "d422" horizontal distance of origin L0.start
  measures "d423" vertical distance of origin L0.start
  measures "d424" horizontal distance of L0.start L0.end
  measures "d425" vertical distance of L0.end L1.end
extrude "Rear_cleat_top" add sketch "Skizze1 (12)" along normal blind 20 separate body makes body 12 in component "Rear_cleat_top"
ref_plane "Arbeitsebene1" through (0, 0, 165.9015) normal (0, 0, 1) x (1, 0, 0) in component "Service_partition"
sketch "Skizze1 (13)" plane through (0, 0, 165.9015) normal (0, 0, 1) x (1, 0, 0) in component "Service_partition"
  line L0 (12, 362) -> (318, 362)
  line L1 (318, 362) -> (318, 548)
  line L2 (318, 548) -> (12, 548)
  line L3 (12, 548) -> (12, 362)
  dimension "d430" = 12
  dimension "d431" = 362
  dimension "d432" = 306
  dimension "d433" = 186
  constraint horizontal L0
  constraint horizontal L2
  constraint vertical L1
  constraint vertical L3
  measures "d430" horizontal distance of origin L0.start
  measures "d431" vertical distance of origin L0.start
  measures "d432" horizontal distance of L0.start L0.end
  measures "d433" vertical distance of L0.end L1.end
extrude "Service_partition" add sketch "Skizze1 (13)" along normal blind 12 separate body makes body 13 in component "Service_partition"
ref_plane "Arbeitsebene1" through (0, 0, 165.9015) normal (0, 0, 1) x (1, 0, 0) in component "Service_floor"
sketch "Skizze1 (14)" plane through (0, 0, 165.9015) normal (0, 0, 1) x (1, 0, 0) in component "Service_floor"
  line L0 (12, 350) -> (318, 350)
  line L1 (318, 350) -> (318, 362)
  line L2 (318, 362) -> (12, 362)
  line L3 (12, 362) -> (12, 350)
  dimension "d438" = 12
  dimension "d439" = 350
  dimension "d440" = 306
  dimension "d441" = 12
  constraint horizontal L0
  constraint horizontal L2
  constraint vertical L1
  constraint vertical L3
  measures "d438" horizontal distance of origin L0.start
  measures "d439" vertical distance of origin L0.start
  measures "d440" horizontal distance of L0.start L0.end
  measures "d441" vertical distance of L0.end L1.end
extrude "Service_floor" add sketch "Skizze1 (14)" along normal blind 122.0985 separate body makes body 14 in component "Service_floor"
ref_plane "Arbeitsebene1" through (0, 0, 200) normal (0, 0, 1) x (1, 0, 0) in component "Brace_lower"
sketch "Skizze1 (15)" plane through (0, 0, 200) normal (0, 0, 1) x (1, 0, 0) in component "Brace_lower"
  line L0 (12, 140) -> (318, 140)
  line L1 (318, 140) -> (318, 160)
  line L2 (318, 160) -> (12, 160)
  line L3 (12, 160) -> (12, 140)
  dimension "d446" = 12
  dimension "d447" = 140
  dimension "d448" = 306
  dimension "d449" = 20
  constraint horizontal L0
  constraint horizontal L2
  constraint vertical L1
  constraint vertical L3
  measures "d446" horizontal distance of origin L0.start
  measures "d447" vertical distance of origin L0.start
  measures "d448" horizontal distance of L0.start L0.end
  measures "d449" vertical distance of L0.end L1.end
extrude "Brace_lower" add sketch "Skizze1 (15)" along normal blind 12 separate body makes body 15 in component "Brace_lower"
ref_plane "Arbeitsebene1" through (0, 0, 0) normal (0, 0, 1) x (1, 0, 0) in component "Port_round_candidate"
sketch "Skizze1 (16)" plane through (0, 0, 0) normal (0, 0, 1) x (1, 0, 0) in component "Port_round_candidate"
  circle A0 centre (165, 70) radius 48.4864
  circle A1 centre (165, 70) radius 45.4864
  dimension "d454" = 165
  dimension "d455" = 70
  dimension "d456" = 96.9728
  dimension "d457" = 90.9728
  constraint concentric A0 A1
  measures "d454" horizontal distance of origin A0.centre
  measures "d455" vertical distance of origin A0.centre
  measures "d456" diameter of A0
  measures "d457" diameter of A1
extrude "Port_tube" add sketch "Skizze1 (16)" along normal blind 161.4786 separate body makes body 16 in component "Port_round_candidate"
ref_plane "Arbeitsebene1" through (0, 0, -8) normal (0, 0, 1) x (1, 0, 0) in component "REF_Faital_10FE200_4ohm_DATASHEET_ENVELOPE"
sketch "Skizze1 (17)" plane through (0, 0, -8) normal (0, 0, 1) x (1, 0, 0) in component "REF_Faital_10FE200_4ohm_DATASHEET_ENVELOPE"
  circle A0 centre (165, 260) radius 128.4
  circle A1 centre (165, 260) radius 116.65
  dimension "d462" = 165
  dimension "d463" = 260
  dimension "d464" = 256.8
  dimension "d465" = 233.3
  constraint concentric A0 A1
  measures "d462" horizontal distance of origin A0.centre
  measures "d463" vertical distance of origin A0.centre
  measures "d464" diameter of A0
  measures "d465" diameter of A1
extrude "LF_flange_envelope" add sketch "Skizze1 (17)" along normal blind 8 separate body makes body 17 in component "REF_Faital_10FE200_4ohm_DATASHEET_ENVELOPE"
ref_plane "Arbeitsebene2" through (0, 0, 0) normal (0, 0, 1) x (1, 0, 0) in component "REF_Faital_10FE200_4ohm_DATASHEET_ENVELOPE"
sketch "Skizze2 (4)" plane through (0, 0, 0) normal (0, 0, 1) x (1, 0, 0) in component "REF_Faital_10FE200_4ohm_DATASHEET_ENVELOPE"
  circle A0 centre (165, 260) radius 115.9
  dimension "d470" = 165
  dimension "d471" = 260
  dimension "d472" = 231.8
  measures "d470" horizontal distance of origin A0.centre
  measures "d471" vertical distance of origin A0.centre
  measures "d472" diameter of A0
ref_plane "Arbeitsebene3" through (0, 0, 59.3) normal (0, 0, 1) x (1, 0, 0) in component "REF_Faital_10FE200_4ohm_DATASHEET_ENVELOPE"
sketch "Skizze3 (4)" plane through (0, 0, 59.3) normal (0, 0, 1) x (1, 0, 0) in component "REF_Faital_10FE200_4ohm_DATASHEET_ENVELOPE"
  circle A0 centre (165, 260) radius 57.65
  dimension "d475" = 165
  dimension "d476" = 260
  dimension "d477" = 115.3
  measures "d475" horizontal distance of origin A0.centre
  measures "d476" vertical distance of origin A0.centre
  measures "d477" diameter of A0
loft "Basket_clearance_frustum_NOT_SOLID_MATERIAL" add profiles "Skizze2 (4)", "Skizze3 (4)" section 1 section 2 separate body makes body 18 in component "REF_Faital_10FE200_4ohm_DATASHEET_ENVELOPE"
ref_plane "Arbeitsebene4" through (0, 0, 59.3) normal (0, 0, 1) x (1, 0, 0) in component "REF_Faital_10FE200_4ohm_DATASHEET_ENVELOPE"
sketch "Skizze4 (4)" plane through (0, 0, 59.3) normal (0, 0, 1) x (1, 0, 0) in component "REF_Faital_10FE200_4ohm_DATASHEET_ENVELOPE"
  circle A0 centre (165, 260) radius 57.65
  dimension "d480" = 165
  dimension "d481" = 260
  dimension "d482" = 115.3
  measures "d480" horizontal distance of origin A0.centre
  measures "d481" vertical distance of origin A0.centre
  measures "d482" diameter of A0
extrude "Magnet_envelope" add sketch "Skizze4 (4)" along normal blind 34.7 separate body makes body 19 in component "REF_Faital_10FE200_4ohm_DATASHEET_ENVELOPE"
ref_plane "Arbeitsebene1" through (0, 0, -5.5) normal (0, 0, 1) x (1, 0, 0) in component "REF_BC_ME10V3_DATASHEET_ENVELOPE"
sketch "Skizze1 (18)" plane through (0, 0, -5.5) normal (0, 0, 1) x (1, 0, 0) in component "REF_BC_ME10V3_DATASHEET_ENVELOPE"
  line L0 (99.75, 404.75) -> (230.25, 404.75)
  line L1 (230.25, 404.75) -> (230.25, 535.25)
  line L2 (230.25, 535.25) -> (99.75, 535.25)
  line L3 (99.75, 535.25) -> (99.75, 404.75)
  dimension "d487" = 99.75
  dimension "d488" = 404.75
  dimension "d489" = 130.5
  dimension "d490" = 130.5
  constraint horizontal L0
  constraint horizontal L2
  constraint vertical L1
  constraint vertical L3
  measures "d487" horizontal distance of origin L0.start
  measures "d488" vertical distance of origin L0.start
  measures "d489" horizontal distance of L0.start L0.end
  measures "d490" vertical distance of L0.end L1.end
extrude "Horn_flange_envelope" add sketch "Skizze1 (18)" along normal blind 5.5 separate body makes body 20 in component "REF_BC_ME10V3_DATASHEET_ENVELOPE"
ref_plane "Arbeitsebene2" through (0, 0, -5.5) normal (0, 0, 1) x (1, 0, 0) in component "REF_BC_ME10V3_DATASHEET_ENVELOPE"
sketch "Skizze2 (5)" plane through (0, 0, -5.5) normal (0, 0, 1) x (1, 0, 0) in component "REF_BC_ME10V3_DATASHEET_ENVELOPE"
  line L0 (113, 418) -> (217, 418)
  line L1 (217, 418) -> (217, 522)
  line L2 (217, 522) -> (113, 522)
  line L3 (113, 522) -> (113, 418)
  dimension "d495" = 113
  dimension "d496" = 418
  dimension "d497" = 104
  dimension "d498" = 104
  constraint horizontal L0
  constraint horizontal L2
  constraint vertical L1
  constraint vertical L3
  measures "d495" horizontal distance of origin L0.start
  measures "d496" vertical distance of origin L0.start
  measures "d497" horizontal distance of L0.start L0.end
  measures "d498" vertical distance of L0.end L1.end
extrude "Horn_mouth_open" cut sketch "Skizze2 (5)" along normal blind 5.5 bodies 20 in component "REF_BC_ME10V3_DATASHEET_ENVELOPE"
ref_plane "Arbeitsebene3" through (0, 0, 0) normal (0, 0, 1) x (1, 0, 0) in component "REF_BC_ME10V3_DATASHEET_ENVELOPE"
sketch "Skizze3 (5)" plane through (0, 0, 0) normal (0, 0, 1) x (1, 0, 0) in component "REF_BC_ME10V3_DATASHEET_ENVELOPE"
  line L0 (113, 418) -> (217, 418)
  line L1 (217, 418) -> (217, 522)
  line L2 (217, 522) -> (113, 522)
  line L3 (113, 522) -> (113, 418)
  dimension "d503" = 113
  dimension "d504" = 418
  dimension "d505" = 104
  dimension "d506" = 104
  constraint horizontal L0
  constraint horizontal L2
  constraint vertical L1
  constraint vertical L3
  measures "d503" horizontal distance of origin L0.start
  measures "d504" vertical distance of origin L0.start
  measures "d505" horizontal distance of L0.start L0.end
  measures "d506" vertical distance of L0.end L1.end
ref_plane "Arbeitsebene4" through (0, 0, 84.5) normal (0, 0, 1) x (1, 0, 0) in component "REF_BC_ME10V3_DATASHEET_ENVELOPE"
sketch "Skizze4 (5)" plane through (0, 0, 84.5) normal (0, 0, 1) x (1, 0, 0) in component "REF_BC_ME10V3_DATASHEET_ENVELOPE"
  circle A0 centre (165, 470) radius 12.5
  dimension "d509" = 165
  dimension "d510" = 470
  dimension "d511" = 25
  measures "d509" horizontal distance of origin A0.centre
  measures "d510" vertical distance of origin A0.centre
  measures "d511" diameter of A0
loft "Flare_clearance_ONLY_not_acoustic_surface" add profiles "Skizze3 (5)", "Skizze4 (5)" section 1 section 2 separate body makes body 21 in component "REF_BC_ME10V3_DATASHEET_ENVELOPE"
ref_plane "Arbeitsebene1" through (0, 0, 84.5) normal (0, 0, 1) x (1, 0, 0) in component "REF_BC_DE10_DATASHEET_ENVELOPE"
sketch "Skizze1 (19)" plane through (0, 0, 84.5) normal (0, 0, 1) x (1, 0, 0) in component "REF_BC_DE10_DATASHEET_ENVELOPE"
  circle A0 centre (165, 470) radius 45
  dimension "d514" = 165
  dimension "d515" = 470
  dimension "d516" = 90
  measures "d514" horizontal distance of origin A0.centre
  measures "d515" vertical distance of origin A0.centre
  measures "d516" diameter of A0
extrude "DE10_cylinder_envelope" add sketch "Skizze1 (19)" along normal blind 53 separate body makes body 22 in component "REF_BC_DE10_DATASHEET_ENVELOPE"
ref_plane "Arbeitsebene1" through (0, 0, 187.9015) normal (0, 0, 1) x (1, 0, 0) in component "RESERVE_amp_wiring_UNVERIFIED_no_mounting_holes"
sketch "Skizze1 (20)" plane through (0, 0, 187.9015) normal (0, 0, 1) x (1, 0, 0) in component "RESERVE_amp_wiring_UNVERIFIED_no_mounting_holes"
  line L0 (110, 372) -> (220, 372)
  line L1 (220, 372) -> (220, 482)
  line L2 (220, 482) -> (110, 482)
  line L3 (110, 482) -> (110, 372)
  dimension "d521" = 110
  dimension "d522" = 372
  dimension "d523" = 110
  dimension "d524" = 110
  constraint horizontal L0
  constraint horizontal L2
  constraint vertical L1
  constraint vertical L3
  measures "d521" horizontal distance of origin L0.start
  measures "d522" vertical distance of origin L0.start
  measures "d523" horizontal distance of L0.start L0.end
  measures "d524" vertical distance of L0.end L1.end
extrude "Amp_space_reserve" add sketch "Skizze1 (20)" along normal blind 40 separate body makes body 23 in component "RESERVE_amp_wiring_UNVERIFIED_no_mounting_holes"
ref_plane "Arbeitsebene2" through (0, 0, 268) normal (0, 0, 1) x (1, 0, 0) in component "Service_floor"
sketch "Skizze2 (6)" plane through (0, 0, 268) normal (0, 0, 1) x (1, 0, 0) in component "Service_floor"
  line L0 (12, 350) -> (32, 350)
  line L1 (32, 350) -> (32, 362)
  line L2 (32, 362) -> (12, 362)
  line L3 (12, 362) -> (12, 350)
ref_plane "Arbeitsebene3" through (0, 0, 268) normal (0, 0, 1) x (1, 0, 0) in component "Service_floor"
sketch "Skizze3 (6)" plane through (0, 0, 268) normal (0, 0, 1) x (1, 0, 0) in component "Service_floor"
  line L0 (298, 350) -> (318, 350)
  line L1 (318, 350) -> (318, 362)
  line L2 (318, 362) -> (298, 362)
  line L3 (298, 362) -> (298, 350)
ref_plane "Arbeitsebene2" through (0, 0, 288) normal (0, 0, 1) x (1, 0, 0) in component "Rear_removable"
sketch "Skizze3 (7)" plane through (0, 0, 288) normal (0, 0, 1) x (1, 0, 0) in component "Rear_removable"
  circle A0 centre (22, 84) radius 2.75
  dimension "d551" = 22
  dimension "d552" = 84
  dimension "d553" = 5.5
  measures "d551" horizontal distance of origin A0.centre
  measures "d552" vertical distance of origin A0.centre
  measures "d553" diameter of A0
extrude "Rear_M5_through_left_0.15" cut sketch "Skizze3 (7)" along normal blind 12 bodies 6 in component "Rear_removable"
ref_plane "Arbeitsebene2" through (0, 0, 268) normal (0, 0, 1) x (1, 0, 0) in component "Rear_cleat_left"
sketch "Skizze3 (8)" plane through (0, 0, 268) normal (0, 0, 1) x (1, 0, 0) in component "Rear_cleat_left"
  circle A0 centre (22, 84) radius 2.75
  dimension "d558" = 22
  dimension "d559" = 84
  dimension "d560" = 5.5
  measures "d558" horizontal distance of origin A0.centre
  measures "d559" vertical distance of origin A0.centre
  measures "d560" diameter of A0
ref_plane "Arbeitsebene1" through (0, 0, 263) normal (0, 0, 1) x (1, 0, 0) in component "Rear_thread_plate_left_0.15"
sketch "Skizze1 (21)" plane through (0, 0, 263) normal (0, 0, 1) x (1, 0, 0) in component "Rear_thread_plate_left_0.15"
  line L0 (12, 64) -> (32, 64)
  line L1 (32, 64) -> (32, 104)
  line L2 (32, 104) -> (12, 104)
  line L3 (12, 104) -> (12, 64)
  dimension "d565" = 12
  dimension "d566" = 64
  dimension "d567" = 20
  dimension "d568" = 40
  constraint horizontal L0
  constraint horizontal L2
  constraint vertical L1
  constraint vertical L3
  measures "d565" horizontal distance of origin L0.start
  measures "d566" vertical distance of origin L0.start
  measures "d567" horizontal distance of L0.start L0.end
  measures "d568" vertical distance of L0.end L1.end
extrude "Steel_plate_M5_tap_after_drilling" add sketch "Skizze1 (21)" along normal blind 5 separate body makes body 24 in component "Rear_thread_plate_left_0.15"
ref_plane "Arbeitsebene2" through (0, 0, 263) normal (0, 0, 1) x (1, 0, 0) in component "Rear_thread_plate_left_0.15"